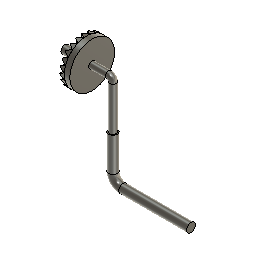
rotary gear (Autodesk Fusion 360 design; units mm, degrees)
part number: 2026-03-28-01-42-28-752
Autodesk Fusion 360 part; units mm, degrees
sketch "Sketch1" plane through (0, 0, 0) normal (1, 0, 0) x (0, 1, 0)
  circle A0 centre (0, 0) radius 3
  dimension "d1" = 6
  constraint coincident A0.centre origin
  measures "d1" diameter of A0
extrude "Extrude1" add sketch "Sketch1" along normal blind 16
sketch "Sketch2" plane through (16, 0, 0) normal (1, 0, 0) x (0, 1, 0)
  circle A0 centre (0, 0) radius 3
  circle A1 centre (0, 0) radius 16.5
  dimension "d4" = 33
  constraint coincident A0.centre A1.centre
  measures "d4" diameter of A1
extrude "Extrude2" add sketch "Sketch2" along normal blind 4 contours A0 | A1
sketch "Sketch3" plane through (0, 0, 0) normal (0, 0, 1) x (1, 0, 0)
  line L0 (16, -2.3221) -> (16, 2.2967)
  line L1 (16, 2.2967) -> (12, -0.0127)
  line L2 (12, -0.0127) -> (16, -2.3221)
  line L3 (16, -16.5) -> (16, 16.5)
  point P0 (14.6667, -0.0127)
  dimension "d7" = 4
  constraint vertical L0
  constraint coincident L0.start L3
  measures "d7" horizontal distance of L0.start L1.end
extrude "Extrude3" add sketch "Sketch3" along normal blind 4 from surface at 12.5
fillet "Fillet2" radius 0.5 1 edges at (12, -0.0127, 14.5)
pattern_circular "C-Pattern2" count 23 over 360 about axis through (1.75, 0, 0) along (1, 0, 0) of "Extrude3", "Fillet2"
sketch "Sketch4" plane through (20, 0, 0) normal (1, 0, 0) x (0, 1, 0)
  circle A0 centre (0, 0) radius 2.5
  circle A1 centre (0, 0) radius 16.5
  dimension "d19" = 5
  constraint coincident A0.centre A1.centre
  measures "d19" diameter of A0
extrude "Extrude4" add sketch "Sketch4" along normal blind 5 contours A0
extrude "Extrude5" add 1 faces at (25, -0.8863, 0.2321) along direction (1, 0, 0) blind 5
ref_plane "WorkPlane1" through (27.1761, 0, -2.5) normal (0, 0, -1) x (0, -1, 0)
sketch "Sketch6" plane through (30, 0, 0) normal (1, 0, 0) x (0, 1, 0)
  circle A0 centre (0, 0) radius 2.5
sketch "Sketch7" plane through (0, 0, 0) normal (0, 1, 0) x (1, 0, 0)
  line L0 (30, 0) -> (32.3663, 0)
  arc A0 (32.3663, 0) -> (35.3663, 3) centre (32.3663, 3) ccw
  line L1 (35.3663, 3) -> (35.3663, 5)
  point P0 (30, 0)
  dimension "d28" = 3
  dimension "d29" = 2
  constraint horizontal L0
  constraint tangent L0 A0
  constraint coincident P0 L0.start
  constraint tangent A0 L1
  constraint vertical L1
  measures "d28" radius of A0
  measures "d29" distance of A0.end L1.end
sweep "Sweep1" add profiles "Sketch6" path "Sketch7" along L0 A0 L1 section 1
extrude "Extrude6" add 1 faces at (36.1973, 0.9769, -5) along direction (0, 0, -1) blind 50
sketch "Sketch8" plane through (0, 0, -55) normal (0, 0, -1) x (1, 0, 0)
  circle A0 centre (35.3663, 0) radius 2.5
  circle A1 centre (35.3663, 0) radius 3.25
  dimension "d38" = 6.5
  constraint concentric A0 A1
  measures "d38" diameter of A1
extrude "Extrude7" add sketch "Sketch8" against normal blind 20
sketch "Sketch9" plane through (0, 0, -55) normal (0, 0, -1) x (1, 0, 0)
  circle A0 centre (35.3663, 0) radius 3.25
sketch "Sketch10" plane through (0, 0, 0) normal (0, 1, 0) x (1, 0, 0)
  line L0 (35.3663, 55) -> (35.3663, 60)
  arc A0 (42.8663, 67.5) -> (35.3663, 60) centre (42.8663, 60) ccw
  line L1 (42.8663, 67.5) -> (92.8663, 67.5)
  point P0 (35.3663, 55)
  dimension "d43" = 15
  dimension "d44" = 50
  dimension "d45" = 5
  constraint vertical L0
  constraint tangent L0 A0
  constraint coincident P0 L0.start
  constraint tangent A0 L1
  measures "d43" diameter of A0
  measures "d44" distance of A0.start L1.end
  measures "d45" distance of P0 L0.end
sketch "Sketch11" plane through (0, 0, -55) normal (0, 0, -1) x (1, 0, 0)
  circle A0 centre (35.3663, 0) radius 3.25
sweep "Sweep2" add profiles "Sketch9" path "Sketch10" along L1 A0 L0 section 1
